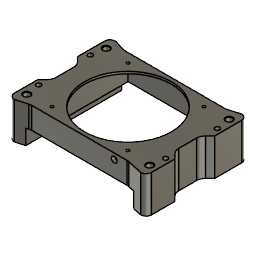
MPPT150_120fan - Size M (Autodesk Fusion 360 design; units mm, degrees)
Autodesk Fusion 360 part; units mm, degrees
sketch "Skizze1" plane through (0, 0, 0) normal (0, 0, 1) x (1, 0, 0)
  line L0 (-87.5, 70) -> (87.5, 70)
  line L1 (95, 62.5) -> (95, -62.5)
  line L2 (87.5, -70) -> (-87.5, -70)
  line L3 (-95, -62.5) -> (-95, 62.5)
  line L4 (0, 70) -> (0, -70) construction
  line L5 (-95, 0) -> (95, 0) construction
  arc A0 (-87.5, 70) -> (-95, 62.5) centre (-87.5, 62.5) ccw
  arc A1 (95, 62.5) -> (87.5, 70) centre (87.5, 62.5) ccw
  arc A2 (87.5, -70) -> (95, -62.5) centre (87.5, -62.5) ccw
  arc A3 (-95, -62.5) -> (-87.5, -70) centre (-87.5, -62.5) ccw
  point P0 (-95, 70)
  point P1 (95, 70)
  point P2 (-95, -70)
  dimension "d1" = 190
  dimension "d2" = 140
  dimension "d3" = 7.5
  constraint horizontal L0
  constraint vertical L1
  constraint horizontal L2
  constraint vertical L3
  constraint midpoint L4 origin
  constraint coincident L0 L4.start
  constraint coincident L3 L5.start
  constraint coincident P0 L0
  constraint coincident P0 L3
  constraint tangent L0 A0
  constraint tangent L3 A0
  constraint coincident L1 L5.end
  constraint coincident P1 L0
  constraint coincident P1 L1
  constraint tangent L0 A1
  constraint tangent L1 A1
  constraint equal A0 A1
  constraint coincident L2 L4.end
  constraint tangent L1 A2
  constraint tangent L2 A2
  constraint equal A0 A2
  constraint coincident P2 L2
  constraint coincident P2 L3
  constraint tangent L2 A3
  constraint tangent L3 A3
  constraint equal A0 A3
  measures "d1" distance of P0 P1
  measures "d2" distance of P0 P2
  measures "d3" radius of A0
extrude "Extrusion1" add sketch "Skizze1" along normal blind 51
sketch "Skizze2" plane through (0, 0, 51) normal (0, 0, 1) x (-1, 0, 0)
  arc A0 (87.5, -70) -> (95, -62.5) centre (87.5, -62.5) ccw
  line L0 (95, -62.5) -> (95, 62.5)
  arc A1 (95, 62.5) -> (87.5, 70) centre (87.5, 62.5) ccw
  line L1 (87.5, 70) -> (-87.5, 70)
  arc A2 (-87.5, 70) -> (-95, 62.5) centre (-87.5, 62.5) ccw
  line L2 (-95, 62.5) -> (-95, -62.5)
  arc A3 (-95, -62.5) -> (-87.5, -70) centre (-87.5, -62.5) ccw
  line L3 (-87.5, -70) -> (87.5, -70)
  line L4 (85, -55) -> (-85, -55) construction
  line L5 (-85, -55) -> (-85, 55) construction
  line L6 (-85, 55) -> (85, 55) construction
  line L7 (85, 55) -> (85, -55) construction
  line L8 (0, -55) -> (0, 55) construction
  line L9 (85, 0) -> (-85, 0) construction
  dimension "d6" = 170
  dimension "d7" = 110
  constraint horizontal L4
  constraint vertical L5
  constraint horizontal L6
  constraint vertical L7
  constraint midpoint L4 L8.start
  constraint midpoint L6 L8.end
  constraint midpoint L7 L9.start
  constraint midpoint L5 L9.end
  constraint midpoint L9 origin
  measures "d6" distance of L4.start L4.end
  measures "d7" distance of L4.start L6.end
hole "Bohrung1" at (-85, -55, 51) at (85, -55, 51) at (85, 55, 51) at (-85, 55, 51) direction (0, 0, -1) diameter 8.5 depth 51 tip angle 118
sketch "Skizze3" plane through (0, 0, 51) normal (0, 0, 1) x (-1, 0, 0)
  circle A0 centre (-85, -55) radius 4.25
  circle A1 centre (85, 55) radius 4.25
  circle A2 centre (-85, 55) radius 4.25
  circle A3 centre (85, -55) radius 4.25
  arc A4 (87.5, -70) -> (95, -62.5) centre (87.5, -62.5) ccw
  line L0 (95, -62.5) -> (95, 62.5)
  arc A5 (95, 62.5) -> (87.5, 70) centre (87.5, 62.5) ccw
  line L1 (87.5, 70) -> (-87.5, 70)
  arc A6 (-87.5, 70) -> (-95, 62.5) centre (-87.5, 62.5) ccw
  line L2 (-95, 62.5) -> (-95, -62.5)
  arc A7 (-95, -62.5) -> (-87.5, -70) centre (-87.5, -62.5) ccw
  line L3 (-87.5, -70) -> (87.5, -70)
  line L4 (88, -35.75) -> (-88, -35.75) construction
  line L5 (-88, -35.75) -> (-88, 35.75) construction
  line L6 (-88, 35.75) -> (88, 35.75) construction
  line L7 (88, 35.75) -> (88, -35.75) construction
  line L8 (0, -35.75) -> (0, 35.75) construction
  line L9 (88, 0) -> (-88, 0) construction
  dimension "d11" = 176
  dimension "d12" = 71.5
  constraint horizontal L4
  constraint vertical L5
  constraint horizontal L6
  constraint vertical L7
  constraint midpoint L4 L8.start
  constraint midpoint L6 L8.end
  constraint midpoint L7 L9.start
  constraint midpoint L5 L9.end
  constraint midpoint L8 origin
  measures "d11" distance of L4.start L4.end
  measures "d12" distance of L4.start L6.end
hole "Bohrung2" at (-88, 35.75, 51) at (-88, -35.75, 51) at (88, -35.75, 51) at (88, 35.75, 51) direction (0, 0, -1) diameter 6.5 depth 51 tip angle 118
hole "Bohrung3" at (0, 0, 51) direction (0, 0, -1) diameter 120 depth 51 tip angle 180
sketch "Skizze4" plane through (0, 0, 0) normal (0, 0, -1) x (1, 0, 0)
  circle A0 centre (0, 0) radius 60
  circle A1 centre (88, 35.75) radius 3.25
  circle A2 centre (-88, -35.75) radius 3.25
  circle A3 centre (-88, 35.75) radius 3.25
  circle A4 centre (88, -35.75) radius 3.25
  circle A5 centre (85, -55) radius 4.25
  circle A6 centre (-85, 55) radius 4.25
  circle A7 centre (85, 55) radius 4.25
  circle A8 centre (-85, -55) radius 4.25
  arc A9 (-95, -62.5) -> (-87.5, -70) centre (-87.5, -62.5) ccw
  line L0 (-87.5, -70) -> (87.5, -70)
  arc A10 (87.5, -70) -> (95, -62.5) centre (87.5, -62.5) ccw
  line L1 (95, -62.5) -> (95, 62.5)
  arc A11 (95, 62.5) -> (87.5, 70) centre (87.5, 62.5) ccw
  line L2 (87.5, 70) -> (-87.5, 70)
  arc A12 (-87.5, 70) -> (-95, 62.5) centre (-87.5, 62.5) ccw
  line L3 (-95, 62.5) -> (-95, -62.5)
  line L4 (-60, 60) -> (60, 60)
  line L5 (60, 60) -> (60, -60)
  line L6 (60, -60) -> (-60, -60)
  line L7 (-60, -60) -> (-60, 60)
  line L8 (0, 60) -> (0, -60) construction
  line L9 (-60, 0) -> (60, 0) construction
  dimension "d19" = 120
  dimension "d20" = 120
  constraint horizontal L4
  constraint vertical L5
  constraint horizontal L6
  constraint vertical L7
  constraint midpoint L4 L8.start
  constraint midpoint L6 L8.end
  constraint midpoint L7 L9.start
  constraint midpoint L5 L9.end
  constraint midpoint L8 A0.centre
  constraint coincident A0.centre origin
  measures "d19" distance of L4.start L4.end
  measures "d20" distance of L4.start L6.end
extrude "Extrusion2" cut sketch "Skizze4" against normal blind 48 contours A0 L5 L6 | A0 L4 L5 | A0 L4 L7 | A0 L6 L7
sketch "Skizze5" plane through (0, 0, 48) normal (0, 0, -1) x (1, 0, 0)
  line L0 (0, 60) -> (-60, 60)
  line L1 (-60, 60) -> (-60, 0)
  arc A0 (0, 60) -> (-60, 0) centre (0, 0) ccw
  line L2 (-52.5, 52.5) -> (52.5, 52.5) construction
  line L3 (52.5, 52.5) -> (52.5, -52.5) construction
  line L4 (52.5, -52.5) -> (-52.5, -52.5) construction
  line L5 (-52.5, -52.5) -> (-52.5, 52.5) construction
  line L6 (0, 52.5) -> (0, -52.5) construction
  line L7 (-52.5, 0) -> (52.5, 0) construction
  dimension "d23" = 105
  dimension "d24" = 105
  constraint horizontal L2
  constraint vertical L3
  constraint horizontal L4
  constraint vertical L5
  constraint midpoint L2 L6.start
  constraint midpoint L4 L6.end
  constraint midpoint L5 L7.start
  constraint midpoint L3 L7.end
  constraint midpoint L7 A0.centre
  constraint coincident A0.centre origin
  measures "d23" distance of L2.start L2.end
  measures "d24" distance of L2.start L4.end
hole "Bohrung4" at (-52.5, 52.5, 48) at (-52.5, -52.5, 48) at (52.5, -52.5, 48) at (52.5, 52.5, 48) direction (0, 0, 1) diameter 3.9 depth 51 tip angle 180
sketch "Skizze6" plane through (0, 0, 0) normal (0, 0, -1) x (1, 0, 0)
  line L0 (-60, -60) -> (-60, 60)
  line L1 (-60, 60) -> (60, 60)
  line L2 (60, 60) -> (60, -60)
  line L3 (60, -60) -> (-60, -60)
  circle A0 centre (88, 35.75) radius 3.25
  circle A1 centre (-88, -35.75) radius 3.25
  circle A2 centre (-88, 35.75) radius 3.25
  circle A3 centre (88, -35.75) radius 3.25
  circle A4 centre (85, -55) radius 4.25
  circle A5 centre (-85, 55) radius 4.25
  circle A6 centre (85, 55) radius 4.25
  circle A7 centre (-85, -55) radius 4.25
  arc A8 (-95, -62.5) -> (-87.5, -70) centre (-87.5, -62.5) ccw
  line L4 (-87.5, -70) -> (87.5, -70)
  arc A9 (87.5, -70) -> (95, -62.5) centre (87.5, -62.5) ccw
  line L5 (95, -62.5) -> (95, 62.5)
  arc A10 (95, 62.5) -> (87.5, 70) centre (87.5, 62.5) ccw
  line L6 (87.5, 70) -> (-87.5, 70)
  arc A11 (-87.5, 70) -> (-95, 62.5) centre (-87.5, 62.5) ccw
  line L7 (-95, 62.5) -> (-95, -62.5)
  line L8 (-75, 70) -> (75, 70)
  line L9 (75, 70) -> (75, -70)
  line L10 (75, -70) -> (-75, -70)
  line L11 (-75, -70) -> (-75, 70)
  line L12 (0, 70) -> (0, -70) construction
  line L13 (-75, 0) -> (75, 0) construction
  dimension "d28" = 150
  dimension "d29" = 140
  constraint horizontal L8
  constraint vertical L9
  constraint horizontal L10
  constraint vertical L11
  constraint midpoint L8 L12.start
  constraint midpoint L10 L12.end
  constraint midpoint L11 L13.start
  constraint midpoint L9 L13.end
  constraint midpoint L12 origin
  measures "d28" distance of L8.start L8.end
  measures "d29" distance of L8.start L10.end
extrude "Extrusion3" cut sketch "Skizze6" against normal blind 21 contours L4 L6 L8 L9 L10 L11
sketch "Skizze7" plane through (0, 0, 51) normal (0, 0, 1) x (-1, 0, 0)
  circle A0 centre (-52.5, 52.5) radius 1.95
  circle A1 centre (52.5, -52.5) radius 1.95
  circle A2 centre (52.5, 52.5) radius 1.95
  circle A3 centre (-52.5, -52.5) radius 1.95
  circle A4 centre (0, 0) radius 60
  circle A5 centre (-88, 35.75) radius 3.25
  circle A6 centre (88, -35.75) radius 3.25
  circle A7 centre (88, 35.75) radius 3.25
  circle A8 centre (-88, -35.75) radius 3.25
  circle A9 centre (-85, -55) radius 4.25
  circle A10 centre (85, 55) radius 4.25
  circle A11 centre (-85, 55) radius 4.25
  circle A12 centre (85, -55) radius 4.25
  arc A13 (87.5, -70) -> (95, -62.5) centre (87.5, -62.5) ccw
  line L0 (95, -62.5) -> (95, 62.5)
  arc A14 (95, 62.5) -> (87.5, 70) centre (87.5, 62.5) ccw
  line L1 (87.5, 70) -> (-87.5, 70)
  arc A15 (-87.5, 70) -> (-95, 62.5) centre (-87.5, 62.5) ccw
  line L2 (-95, 62.5) -> (-95, -62.5)
  arc A16 (-95, -62.5) -> (-87.5, -70) centre (-87.5, -62.5) ccw
  line L3 (-87.5, -70) -> (87.5, -70)
  line L4 (87.5, -70) -> (71.6833, -65.481)
  line L5 (-87.5, -70) -> (-71.6833, -65.481)
  line L6 (-68.2493, -65) -> (68.2493, -65)
  line L7 (87.5, 70) -> (71.6833, 65.481)
  line L8 (68.2493, 65) -> (-63.6278, 65)
  line L9 (-66.3395, 65.2977) -> (-87.5, 70)
  line L10 (95, -25) -> (88.6612, -18.6612)
  line L11 (85, -9.8223) -> (85, 14.8223)
  line L12 (88.6612, 23.6612) -> (95, 30)
  line L13 (-95, -25) -> (-88.6612, -18.6612)
  line L14 (-85, -9.8223) -> (-85, 14.8223)
  line L15 (-88.6612, 23.6612) -> (-95, 30)
  arc A17 (68.2493, 65) -> (71.6833, 65.481) centre (68.2493, 77.5) ccw
  arc A18 (-66.3395, 65.2977) -> (-63.6278, 65) centre (-63.6278, 77.5) ccw
  arc A19 (-85, 14.8223) -> (-88.6612, 23.6612) centre (-97.5, 14.8223) ccw
  arc A20 (-88.6612, -18.6612) -> (-85, -9.8223) centre (-97.5, -9.8223) ccw
  arc A21 (-68.2493, -65) -> (-71.6833, -65.481) centre (-68.2493, -77.5) ccw
  arc A22 (71.6833, -65.481) -> (68.2493, -65) centre (68.2493, -77.5) ccw
  arc A23 (85, -9.8223) -> (88.6612, -18.6612) centre (97.5, -9.8223) ccw
  arc A24 (88.6612, 23.6612) -> (85, 14.8223) centre (97.5, 14.8223) ccw
  dimension "d32" = 12.5
  constraint coincident A13.start L3.end
  constraint coincident A16.end L3.start
  constraint parallel L3 L6
  constraint coincident A14.end L1.start
  constraint parallel L5 L7
  constraint perpendicular L0 L8
  constraint coincident L1.end A15.start
  constraint coincident L0 L10.start
  constraint parallel L0 L11
  constraint coincident L0 L12.end
  constraint perpendicular L10 L12
  constraint coincident L2 L13.start
  constraint parallel L12 L13
  constraint parallel L2 L14
  constraint coincident L2 L15.end
  constraint perpendicular L13 L15
  constraint tangent L7 A17
  constraint tangent L8 A17
  constraint tangent L8 A18
  constraint tangent L9 A18
  constraint equal A17 A18
  constraint tangent L14 A19
  constraint tangent L15 A19
  constraint equal A17 A19
  constraint tangent L13 A20
  constraint tangent L14 A20
  constraint equal A17 A20
  constraint tangent L5 A21
  constraint tangent L6 A21
  constraint equal A17 A21
  constraint tangent L4 A22
  constraint tangent L6 A22
  constraint equal A17 A22
  constraint tangent L10 A23
  constraint tangent L11 A23
  constraint equal A17 A23
  constraint tangent L11 A24
  constraint tangent L12 A24
  constraint equal A17 A24
  measures "d32" radius of A17
extrude "Extrusion4" cut sketch "Skizze7" against normal blind 52 contours L3 L4 L5 L6 A21 A22 | L0 L10 L11 L12 A23 A24 | L2 L13 L14 L15 A19 A20 | L1 L7 L8 L9 A17 A18
hole "Bohrung5" at (46.0038, -60, 43.024) direction (0, -1, 0) diameter 8 depth 51 tip angle 180
sketch "Skizze8" plane through (0, 0, 0) normal (0, 0, -1) x (1, 0, 0)
  line L0 (-88.6612, -18.6612) -> (-95, -25)
  line L1 (-95, -25) -> (-95, -62.5)
  arc A0 (-95, -62.5) -> (-87.5, -70) centre (-87.5, -62.5) ccw
  line L2 (-87.5, -70) -> (-75, -66.4286)
  line L3 (-75, -66.4286) -> (-75, 66.4286)
  line L4 (-75, 66.4286) -> (-87.5, 70)
  arc A1 (-87.5, 70) -> (-95, 62.5) centre (-87.5, 62.5) ccw
  line L5 (-95, 62.5) -> (-95, 30)
  line L6 (-95, 30) -> (-88.6612, 23.6612)
  arc A2 (-85, 14.8223) -> (-88.6612, 23.6612) centre (-97.5, 14.8223) ccw
  line L7 (-85, 14.8223) -> (-85, -9.8223)
  arc A3 (-88.6612, -18.6612) -> (-85, -9.8223) centre (-97.5, -9.8223) ccw
  circle A4 centre (-88, -35.75) radius 3.25
  circle A5 centre (-88, 35.75) radius 3.25
  circle A6 centre (-85, 55) radius 4.25
  circle A7 centre (-85, -55) radius 4.25
  line L8 (-91.0659, 40.8455) -> (-93.9457, 35.6426)
  line L9 (-93.9457, 35.6426) -> (-90.8798, 30.5471)
  line L10 (-90.8798, 30.5471) -> (-84.9341, 30.6545)
  line L11 (-84.9341, 30.6545) -> (-82.0543, 35.8574)
  line L12 (-82.0543, 35.8574) -> (-85.1202, 40.9529)
  line L13 (-85.1202, 40.9529) -> (-91.0659, 40.8455)
  line L14 (-88.003, -29.8033) -> (-93.1515, -32.7792)
  line L15 (-93.1515, -32.7792) -> (-93.1485, -38.7259)
  line L16 (-93.1485, -38.7259) -> (-87.997, -41.6967)
  line L17 (-87.997, -41.6967) -> (-82.8485, -38.7208)
  line L18 (-82.8485, -38.7208) -> (-82.8515, -32.7741)
  line L19 (-82.8515, -32.7741) -> (-88.003, -29.8033)
  point P0 (-88, 35.75)
  point P1 (-88, -35.75)
  dimension "d39" = 5.15
  dimension "d40" = 5.15
  constraint coincident P0 A5.centre
  constraint coincident P1 A4.centre
  measures "d39" distance of P0 L13
  measures "d40" distance of P1 L19
extrude "Extrusion5" cut sketch "Skizze8" against normal blind 5.5 contours L8 L9 L10 L11 L12 L13 | L14 L15 L16 L17 L18 L19
sketch "Skizze9" plane through (0, 0, 0) normal (0, 0, -1) x (1, 0, 0)
  circle A0 centre (88, 35.75) radius 3.25
  circle A1 centre (88, -35.75) radius 3.25
  circle A2 centre (85, -55) radius 4.25
  circle A3 centre (85, 55) radius 4.25
  line L0 (95, -25) -> (88.6612, -18.6612)
  arc A4 (85, -9.8223) -> (88.6612, -18.6612) centre (97.5, -9.8223) ccw
  line L1 (85, -9.8223) -> (85, 14.8223)
  arc A5 (88.6612, 23.6612) -> (85, 14.8223) centre (97.5, 14.8223) ccw
  line L2 (88.6612, 23.6612) -> (95, 30)
  line L3 (95, 30) -> (95, 62.5)
  arc A6 (95, 62.5) -> (87.5, 70) centre (87.5, 62.5) ccw
  line L4 (87.5, 70) -> (75, 67.2222)
  line L5 (75, 67.2222) -> (75, -66.4286)
  line L6 (75, -66.4286) -> (87.5, -70)
  arc A7 (87.5, -70) -> (95, -62.5) centre (87.5, -62.5) ccw
  line L7 (95, -62.5) -> (95, -25)
  line L8 (93.2834, 33.0207) -> (93.0054, 38.9609)
  line L9 (93.0054, 38.9609) -> (87.722, 41.6902)
  line L10 (87.722, 41.6902) -> (82.7166, 38.4793)
  line L11 (82.7166, 38.4793) -> (82.9946, 32.5391)
  line L12 (82.9946, 32.5391) -> (88.278, 29.8098)
  line L13 (88.278, 29.8098) -> (93.2834, 33.0207)
  line L14 (93.15, -32.7766) -> (88, -29.8033)
  line L15 (88, -29.8033) -> (82.85, -32.7766)
  line L16 (82.85, -32.7766) -> (82.85, -38.7234)
  line L17 (82.85, -38.7234) -> (88, -41.6967)
  line L18 (88, -41.6967) -> (93.15, -38.7234)
  line L19 (93.15, -38.7234) -> (93.15, -32.7766)
  point P0 (88, 35.75)
  point P1 (88, -35.75)
  dimension "d43" = 5.15
  dimension "d44" = 5.15
  constraint coincident P0 A0.centre
  constraint coincident P1 A1.centre
  measures "d43" distance of P0 L13
  measures "d44" distance of P1 L19
extrude "Extrusion6" cut sketch "Skizze9" against normal blind 5.5 contours L8 L9 L10 L11 L12 L13 | L14 L15 L16 L17 L18 L19
sketch "Skizze10" plane through (0, 0, 51) normal (0, 0, 1) x (-1, 0, 0)
  circle A0 centre (85, -55) radius 4.25
  circle A1 centre (-85, 55) radius 4.25
  circle A2 centre (85, 55) radius 4.25
  circle A3 centre (-85, -55) radius 4.25
  circle A4 centre (-88, -35.75) radius 3.25
  circle A5 centre (88, 35.75) radius 3.25
  circle A6 centre (88, -35.75) radius 3.25
  circle A7 centre (-88, 35.75) radius 3.25
  circle A8 centre (0, 0) radius 60
  circle A9 centre (-52.5, -52.5) radius 1.95
  circle A10 centre (52.5, 52.5) radius 1.95
  circle A11 centre (52.5, -52.5) radius 1.95
  circle A12 centre (-52.5, 52.5) radius 1.95
  line L0 (95, -25) -> (88.6612, -18.6612)
  arc A13 (85, -9.8223) -> (88.6612, -18.6612) centre (97.5, -9.8223) ccw
  line L1 (85, -9.8223) -> (85, 14.8223)
  arc A14 (88.6612, 23.6612) -> (85, 14.8223) centre (97.5, 14.8223) ccw
  line L2 (88.6612, 23.6612) -> (95, 30)
  line L3 (95, 30) -> (95, 62.5)
  arc A15 (95, 62.5) -> (87.5, 70) centre (87.5, 62.5) ccw
  line L4 (87.5, 70) -> (71.6833, 65.481)
  arc A16 (68.2493, 65) -> (71.6833, 65.481) centre (68.2493, 77.5) ccw
  line L5 (68.2493, 65) -> (-63.6278, 65)
  arc A17 (-66.3395, 65.2977) -> (-63.6278, 65) centre (-63.6278, 77.5) ccw
  line L6 (-66.3395, 65.2977) -> (-87.5, 70)
  arc A18 (-87.5, 70) -> (-95, 62.5) centre (-87.5, 62.5) ccw
  line L7 (-95, 62.5) -> (-95, 30)
  line L8 (-95, 30) -> (-88.6612, 23.6612)
  arc A19 (-85, 14.8223) -> (-88.6612, 23.6612) centre (-97.5, 14.8223) ccw
  line L9 (-85, 14.8223) -> (-85, -9.8223)
  arc A20 (-88.6612, -18.6612) -> (-85, -9.8223) centre (-97.5, -9.8223) ccw
  line L10 (-88.6612, -18.6612) -> (-95, -25)
  line L11 (-95, -25) -> (-95, -62.5)
  arc A21 (-95, -62.5) -> (-87.5, -70) centre (-87.5, -62.5) ccw
  line L12 (-87.5, -70) -> (-71.6833, -65.481)
  arc A22 (-68.2493, -65) -> (-71.6833, -65.481) centre (-68.2493, -77.5) ccw
  line L13 (-68.2493, -65) -> (68.2493, -65)
  arc A23 (71.6833, -65.481) -> (68.2493, -65) centre (68.2493, -77.5) ccw
  line L14 (71.6833, -65.481) -> (87.5, -70)
  arc A24 (87.5, -70) -> (95, -62.5) centre (87.5, -62.5) ccw
  line L15 (95, -62.5) -> (95, -25)
  point P0 (85, -55)
  point P1 (85, 55)
  point P2 (-85, 55)
  point P3 (-85, -55)
  constraint coincident P0 A0.centre
  constraint coincident P1 A2.centre
  constraint coincident A1.centre P2
  constraint coincident P3 A3.centre
hole "Bohrung6" at (-85, 55, 51) at (-85, -55, 51) at (85, -55, 51) at (85, 55, 51) direction (0, 0, -1) diameter 8 depth 51 tip angle 180 countersink diameter 9.8 countersink angle 90
